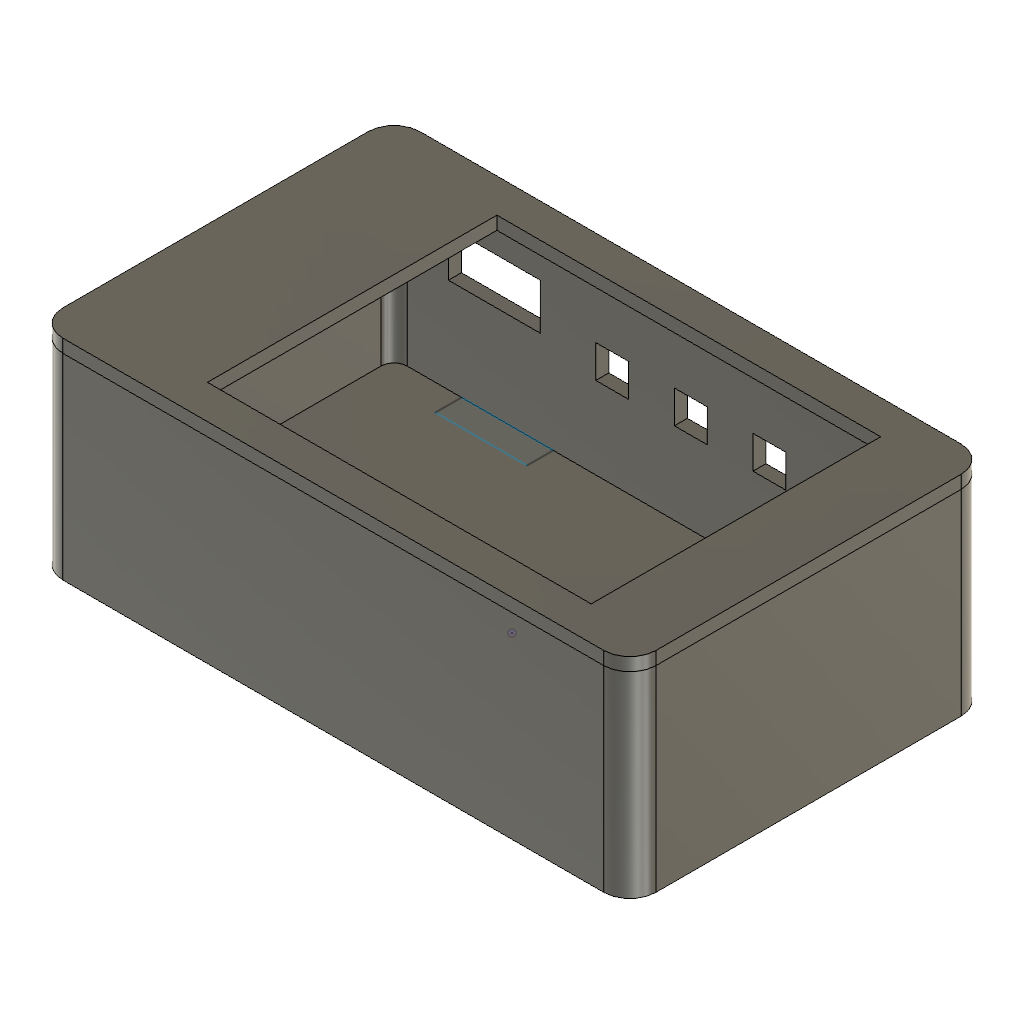
DAYFRAME Case (Autodesk Fusion 360 design; units mm, degrees)
part number: 2026-11-02-08-27-29-024
Autodesk Fusion 360 part; units mm, degrees
sketch "Sketch1" plane through (0, 0, 0) normal (0, 0, 1) x (1, 0, 0)
  line L0 (-41.3, 27.3) -> (41.3, 27.3)
  line L1 (45.3, 23.3) -> (45.3, -23.3)
  line L2 (41.3, -27.3) -> (-41.3, -27.3)
  line L3 (-45.3, -23.3) -> (-45.3, 23.3)
  arc A0 (-41.3, 27.3) -> (-45.3, 23.3) centre (-41.3, 23.3) ccw
  arc A1 (-45.3, -23.3) -> (-41.3, -27.3) centre (-41.3, -23.3) ccw
  arc A2 (41.3, -27.3) -> (45.3, -23.3) centre (41.3, -23.3) ccw
  arc A3 (45.3, 23.3) -> (41.3, 27.3) centre (41.3, 23.3) ccw
  point P0 (-45.3, 27.3)
  point P1 (45.3, 27.3)
  point P2 (45.3, -27.3)
  dimension "d13" = 90.6
  dimension "d14" = 54.6
  dimension "d15" = 4
  dimension "d16" = 4
  dimension "d40" = 45.3
  dimension "d41" = 27.3
  constraint horizontal L0
  constraint vertical L1
  constraint horizontal L2
  constraint vertical L3
  constraint coincident P0 L0
  constraint coincident P0 L3
  constraint tangent L0 A0
  constraint tangent L3 A0
  constraint tangent L2 A1
  constraint tangent L3 A1
  constraint equal A0 A1
  constraint coincident P2 L1
  constraint coincident P2 L2
  constraint tangent L1 A2
  constraint tangent L2 A2
  constraint coincident P1 L0
  constraint coincident P1 L1
  constraint tangent L0 A3
  constraint tangent L1 A3
  constraint equal A2 A3
  measures "d13" distance of P0 P1
  measures "d14" distance of P1 P2
  measures "d15" radius of A0
  measures "d16" radius of A2
  measures "d40" distance of origin L1
  measures "d41" distance of origin L0
extrude "Extrude1" add sketch "Sketch1" along normal blind 30 makes body 1
shell "Shell1" thickness 2 removed faces 1 at (13.7667, -9.1, 30) on bodies 1
sketch "Sketch2" plane through (0, 0, 30) normal (0, 0, 1) x (-1, 0, 0)
  line L0 (-41.3, 25.3) -> (41.3, 25.3)
  arc A0 (43.3, 23.3) -> (41.3, 25.3) centre (41.3, 23.3) ccw
  line L1 (43.3, 23.3) -> (43.3, -23.3)
  arc A1 (41.3, -25.3) -> (43.3, -23.3) centre (41.3, -23.3) ccw
  line L2 (41.3, -25.3) -> (-41.3, -25.3)
  arc A2 (-43.3, -23.3) -> (-41.3, -25.3) centre (-41.3, -23.3) ccw
  line L3 (-43.3, -23.3) -> (-43.3, 23.3)
  arc A3 (-41.3, 25.3) -> (-43.3, 23.3) centre (-41.3, 23.3) ccw
  arc A4 (-41.3, 27.3) -> (-45.3, 23.3) centre (-41.3, 23.3) ccw
  line L4 (-45.3, 23.3) -> (-45.3, -23.3)
  arc A5 (-45.3, -23.3) -> (-41.3, -27.3) centre (-41.3, -23.3) ccw
  line L5 (-41.3, -27.3) -> (41.3, -27.3)
  arc A6 (41.3, -27.3) -> (45.3, -23.3) centre (41.3, -23.3) ccw
  line L6 (45.3, -23.3) -> (45.3, 23.3)
  arc A7 (45.3, 23.3) -> (41.3, 27.3) centre (41.3, 23.3) ccw
  line L7 (41.3, 27.3) -> (-41.3, 27.3)
  line L8 (41.3, -27.3) -> (-41.3, -27.3)
  line L9 (-45.3, -23.3) -> (-45.3, 23.3)
  line L10 (-41.3, 27.3) -> (41.3, 27.3)
  line L11 (45.3, 23.3) -> (45.3, -23.3)
  arc A8 (-45.3, -23.3) -> (-41.3, -27.3) centre (-41.3, -23.3) ccw
  arc A9 (-41.3, 27.3) -> (-45.3, 23.3) centre (-41.3, 23.3) ccw
  arc A10 (45.3, 23.3) -> (41.3, 27.3) centre (41.3, 23.3) ccw
  arc A11 (41.3, -27.3) -> (45.3, -23.3) centre (41.3, -23.3) ccw
  point P0 (45.3, -27.3)
  point P1 (-45.3, -27.3)
  point P2 (45.3, 27.3)
  dimension "d30" = 90.6
  dimension "d31" = 54.6
  dimension "d32" = 4
  dimension "d33" = 4
  dimension "d42" = 45.3
  dimension "d43" = 27.3
  constraint horizontal L8
  constraint vertical L9
  constraint horizontal L10
  constraint vertical L11
  constraint coincident P1 L8
  constraint coincident P1 L9
  constraint tangent L8 A8
  constraint tangent L9 A8
  constraint tangent L9 A9
  constraint tangent L10 A9
  constraint equal A8 A9
  constraint coincident P2 L10
  constraint coincident P2 L11
  constraint tangent L10 A10
  constraint tangent L11 A10
  constraint equal A8 A10
  constraint coincident P0 L8
  constraint coincident P0 L11
  constraint tangent L8 A11
  constraint tangent L11 A11
  measures "d30" distance of P0 P1
  measures "d31" distance of P0 P2
  measures "d32" radius of A8
  measures "d33" radius of A11
  measures "d42" distance of origin L9
  measures "d43" distance of origin L10
extrude "Extrude2" add sketch "Sketch2" along normal blind 2 separate body contours L0 A0 L1 A1 L2 A2 L3 A3 | A4 L4 A5 L5 A6 L6 A7 L7 L8 L9 L10 L11 A8 A9 A10 A11 makes body 2
sketch "Sketch4" plane through (0, 0, 32) normal (0, 0, 1) x (-1, 0, 0)
  arc A0 (45.3, 23.3) -> (41.3, 27.3) centre (41.3, 23.3) ccw
  line L0 (41.3, 27.3) -> (-41.3, 27.3)
  arc A1 (-41.3, 27.3) -> (-45.3, 23.3) centre (-41.3, 23.3) ccw
  line L1 (-45.3, 23.3) -> (-45.3, -23.3)
  arc A2 (-45.3, -23.3) -> (-41.3, -27.3) centre (-41.3, -23.3) ccw
  line L2 (-41.3, -27.3) -> (41.3, -27.3)
  arc A3 (41.3, -27.3) -> (45.3, -23.3) centre (41.3, -23.3) ccw
  line L3 (45.3, -23.3) -> (45.3, 23.3)
  line L4 (-34.2, 22.1) -> (24.4, 22.1)
  line L5 (24.4, 22.1) -> (24.4, -22.1)
  line L6 (24.4, -22.1) -> (-34.2, -22.1)
  line L7 (-34.2, -22.1) -> (-34.2, 22.1)
  dimension "d36" = 58.6
  dimension "d37" = 44.2
  dimension "d38" = 34.2
  dimension "d39" = 22.1
  constraint horizontal L4
  constraint vertical L5
  constraint horizontal L6
  constraint vertical L7
  measures "d36" distance of L5.end L6.end
  measures "d37" distance of L4.end L5.end
  measures "d38" distance of origin L7
  measures "d39" distance of origin L6
extrude "Extrude3" cut sketch "Sketch4" against normal blind 2 contours L4 L5 L6 L7 bodies 2
sketch "Sketch5" plane through (0, 0, 32) normal (0, 0, 1) x (-1, 0, 0)
  line L0 (24.4, 22.1) -> (24.4, -22.1)
  line L1 (24.4, -22.1) -> (-34.2, -22.1)
  line L2 (-34.2, -22.1) -> (-34.2, 22.1)
  line L3 (-34.2, 22.1) -> (24.4, 22.1)
  arc A0 (-45.3, -23.3) -> (-41.3, -27.3) centre (-41.3, -23.3) ccw
  line L4 (-41.3, -27.3) -> (41.3, -27.3)
  arc A1 (41.3, -27.3) -> (45.3, -23.3) centre (41.3, -23.3) ccw
  line L5 (45.3, -23.3) -> (45.3, 23.3)
  arc A2 (45.3, 23.3) -> (41.3, 27.3) centre (41.3, 23.3) ccw
  line L6 (41.3, 27.3) -> (-41.3, 27.3)
  arc A3 (-41.3, 27.3) -> (-45.3, 23.3) centre (-41.3, 23.3) ccw
  line L7 (-45.3, 23.3) -> (-45.3, -23.3)
  circle A4 centre (36.08, -22) radius 1.5
  circle A5 centre (36.08, 22) radius 1.5
  circle A6 centre (-40, -22) radius 1.5
  circle A7 centre (-40, 22) radius 1.5
  dimension "d46" = 3
  dimension "d47" = 22
  dimension "d48" = 36.08
  dimension "d49" = 3
  dimension "d50" = 22
  dimension "d51" = 36.08
  dimension "d52" = 3
  dimension "d53" = 22
  dimension "d54" = 40
  dimension "d55" = 3
  dimension "d56" = 22
  dimension "d57" = 40
  measures "d46" diameter of A4
  measures "d47" vertical distance of origin A4.centre
  measures "d48" horizontal distance of origin A4.centre
  measures "d49" diameter of A5
  measures "d50" vertical distance of origin A5.centre
  measures "d51" horizontal distance of origin A5.centre
  measures "d52" diameter of A6
  measures "d53" vertical distance of origin A6.centre
  measures "d54" horizontal distance of origin A6.centre
  measures "d55" diameter of A7
  measures "d56" vertical distance of origin A7.centre
  measures "d57" horizontal distance of origin A7.centre
extrude "Extrude4" add sketch "Sketch5" against normal blind 6 contours A4 | A5 | A6 | A7 bodies 2
sketch "Sketch6" plane through (0, 0, 0) normal (0, 0, 1) x (1, 0, 0)
  line L0 (-35, 27.3087) -> (-21, 27.3087)
  line L1 (-21, 27.3087) -> (-21, 23.3087)
  line L2 (-21, 23.3087) -> (-35, 23.3087)
  line L3 (-35, 23.3087) -> (-35, 27.3087)
  dimension "d64" = 4
  dimension "d65" = 14
  dimension "d66" = 21
  constraint horizontal L0
  constraint vertical L1
  constraint horizontal L2
  constraint vertical L3
  measures "d64" distance of L0.end L1.end
  measures "d65" distance of L1.end L2.end
  measures "d66" distance of origin L1
extrude "Extrude5" cut sketch "Sketch6" along normal blind 7 from surface at 16.5 bodies 1
sketch "Sketch7" plane through (0, 0, 0) normal (0, 0, 1) x (1, 0, 0)
  line L0 (-12.5, 28) -> (-7.5, 28)
  line L1 (-7.5, 28) -> (-7.5, 24)
  line L2 (-7.5, 24) -> (-12.5, 24)
  line L3 (-12.5, 24) -> (-12.5, 28)
  line L4 (-0.5, 28) -> (4.5, 28)
  line L5 (4.5, 28) -> (4.5, 24)
  line L6 (4.5, 24) -> (-0.5, 24)
  line L7 (-0.5, 24) -> (-0.5, 28)
  line L8 (11.5, 28) -> (16.5, 28)
  line L9 (16.5, 28) -> (16.5, 24)
  line L10 (16.5, 24) -> (11.5, 24)
  line L11 (11.5, 24) -> (11.5, 28)
  dimension "d72" = 4
  dimension "d73" = 5
  dimension "d74" = 28
  dimension "d75" = 7.5
  dimension "d76" = 5
  dimension "d77" = 4
  dimension "d78" = 4.5
  dimension "d79" = 5
  dimension "d80" = 4
  dimension "d81" = 16.5
  constraint horizontal L0
  constraint vertical L1
  constraint horizontal L2
  constraint vertical L3
  constraint horizontal L4
  constraint vertical L5
  constraint horizontal L6
  constraint vertical L7
  constraint horizontal L8
  constraint vertical L9
  constraint horizontal L10
  constraint vertical L11
  measures "d72" distance of L0.end L1.end
  measures "d73" distance of L0.start L0.end
  measures "d74" distance of origin L0
  measures "d75" distance of origin L1
  measures "d76" distance of L4.start L4.end
  measures "d77" distance of L4.end L5.end
  measures "d78" distance of origin L5
  measures "d79" distance of L8.start L8.end
  measures "d80" distance of L8.end L9.end
  measures "d81" distance of origin L9
extrude "Extrude6" cut sketch "Sketch7" along normal blind 5 from surface at 14.5 bodies 1
equation "disp_w = 86 mm" comment "Display module width (long side)"
equation "disp_h = 50 mm" comment "Display module height (short side)"
equation "clr = 0.3 mm" comment "Clearance per side"
equation "wall = 2 mm" comment "Wall thickness"
equation "depth_in = 28 mm" comment "Inner depth"
equation "corner_r = 4 mm" comment "Corner rounding"
equation "inner_w = disp_w + 2 * clr" comment "86.6"
equation "inner_h = disp_h + 2 * clr" comment "50.6"
equation "outer_w = inner_w + 2 * wall" comment "90.6"
equation "outer_h = inner_h + 2 * wall" comment "54.6"
equation "leg_len = 50 mm" comment "Kickstand length"
equation "pin_d = 2 mm" comment "Hinge hole -- 1.75mm filament"
equation "d13 = outer_w"
equation "d14 = outer_h"
equation "d15 = corner_r"
equation "d16 = corner_r"
equation "d17 = depth_in + wall"
equation "d19 = wall"
equation "aa_l = 57.6 mm" comment "Visible screen length"
equation "aa_w = 43.2 mm" comment "Visible screen width"
equation "win_pad = 0.5 mm" comment "Extra gap around screen"
equation "win_l = aa_l + 2 * win_pad" comment "Window length (58.6)"
equation "win_w = aa_w + 2 * win_pad" comment "Window width (44.2)"
equation "peg_d = 3 mm" comment "Diameter of pegs that go thru module's mounting holes (hole 3.2)"
equation "peg_h = 4 mm" comment "How far pegs stick down from bezel"
equation "win_shift = disp_w / 2 - ( 9.3 mm + aa_l / 2 )" comment "How far to move window from centre"
equation "pcb_w = 60 mm" comment "perfboard width"
equation "pcb_h = 40 mm" comment "perfboard height"
equation "d30 = outer_w"
equation "d31 = outer_h"
equation "d32 = corner_r"
equation "d33 = corner_r"
equation "d36 = win_l"
equation "d37 = win_w"
equation "d38 = win_shift + win_l / 2"
equation "d39 = win_w / 2"
equation "d40 = outer_w / 2"
equation "d41 = outer_h / 2"
equation "d42 = outer_w / 2"
equation "d43 = outer_h / 2"
equation "d46 = peg_d"
equation "d49 = peg_d"
equation "d52 = peg_d"
equation "d55 = peg_d"
equation "d58 = -2 mm - peg_h"
equation "usb_w = 14 mm" comment "opening width for plug"
equation "usb_h = 7 mm" comment "opening height"
equation "usb_x = 28 mm" comment "how far left to the middle opening is centred"
equation "usb_z = 10 mm" comment "how far below the rim the opening is centred"
equation "d65 = usb_w"
equation "d66 = usb_x - usb_w / 2"
equation "d67 = depth_in + wall - usb_z - usb_h / 2"
equation "d68 = usb_h"
equation "btn_s = 5 mm" comment "square hole size"
equation "btn_z = 13 mm" comment "how far below the rim the holes are"
equation "d73 = btn_s"
equation "d76 = btn_s"
equation "d79 = btn_s"
